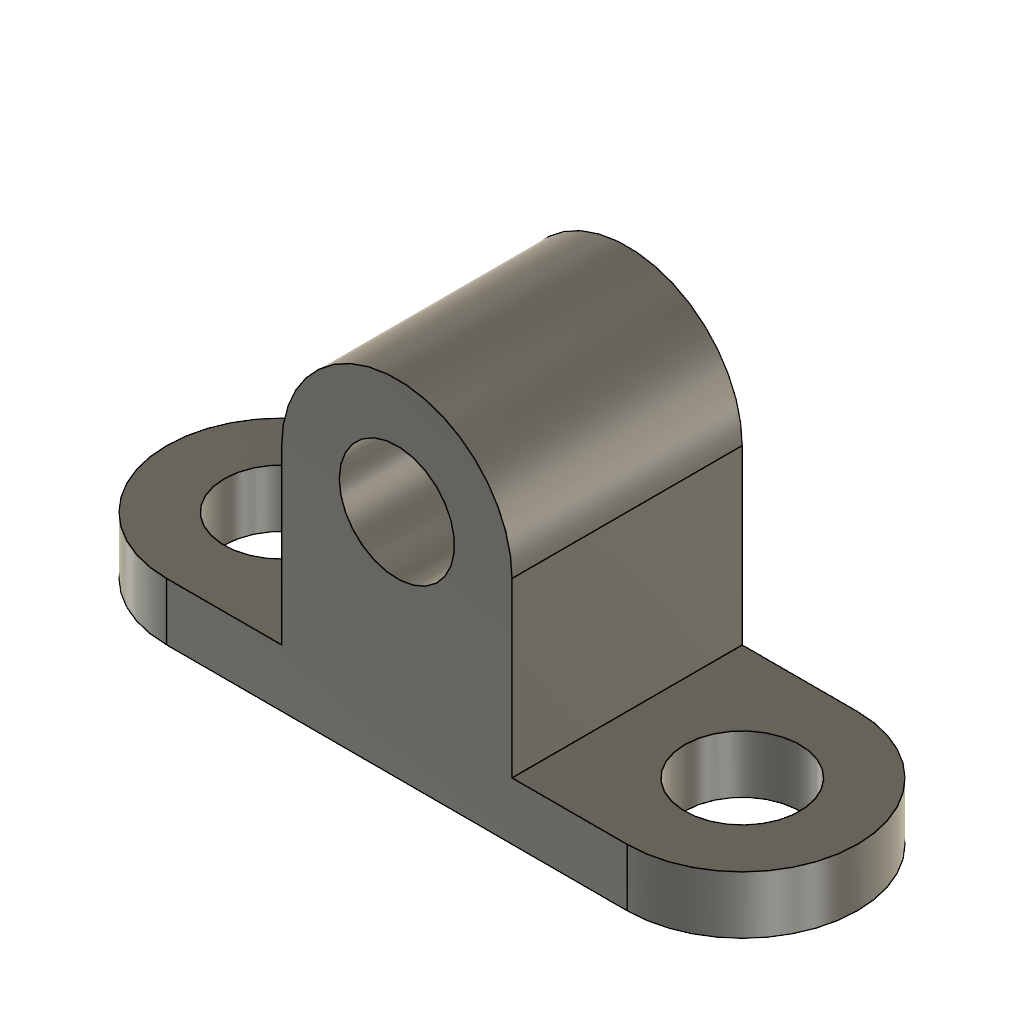
prueba-fusion (Autodesk Fusion 360 design; units mm, degrees)
part number: 2026-10-24-19-08-13-872
Autodesk Fusion 360 part; units mm, degrees
sketch "Boceto1" plane through (0, 0, 0) normal (0, 0, 1) x (1, 0, 0)
  line L0 (0, 0) -> (80, 0)
  line L1 (80, 40) -> (0, 40)
  arc A0 (0, 40) -> (0, 0) centre (0, 20) ccw
  arc A1 (80, 0) -> (80, 40) centre (80, 20) ccw
  circle A2 centre (0, 20) radius 10
  circle A3 centre (80, 20) radius 10
  dimension "d1" = 80
  dimension "d2" = 40
  dimension "d3" = 80
  dimension "d4" = 40
  dimension "d5" = 40
  dimension "d6" = 20
  dimension "d7" = 20
  constraint coincident L0.start A0.end
  constraint horizontal L0
  constraint coincident L0 A0.end
  constraint concentric A0 A2
  constraint concentric A1 A3
  measures "d1" distance of L0.start L0.end
  measures "d2" distance of L0.end L1.start
  measures "d3" distance of L1.start L1.end
  measures "d4" diameter of A1
  measures "d5" diameter of A0
  measures "d6" diameter of A2
  measures "d7" diameter of A3
extrude "Extruir1" add sketch "Boceto1" along normal blind 10
sketch "Boceto2" plane through (0, 0, 0) normal (0, -1, 0) x (1, 0, 0)
  line L0 (0, 0) -> (80, 0)
  line L1 (80, 0) -> (80, 10)
  line L2 (80, 10) -> (0, 10)
  line L3 (0, 10) -> (0, 0)
  line L4 (20, 0) -> (20, 40)
  line L5 (60, 40) -> (60, 0)
  arc A0 (60, 40) -> (20, 40) centre (40, 40) ccw
  circle A1 centre (40, 40) radius 10
  dimension "d11" = 40
  dimension "d12" = 40
  dimension "d13" = 40
  dimension "d14" = 20
  constraint coincident L0 L4.start
  constraint perpendicular L2 L4
  constraint coincident L0 L5.end
  constraint perpendicular L0 L5
  constraint concentric A0 A1
  measures "d11" distance of L4.start L4.end
  measures "d12" distance of L4.end L5.start
  measures "d13" diameter of A0
  measures "d14" diameter of A1
extrude "Extruir2" add sketch "Boceto2" against normal blind 40 contours L2 L4 L5 A0
equation "d15 = 0 mm - 40 mm"
